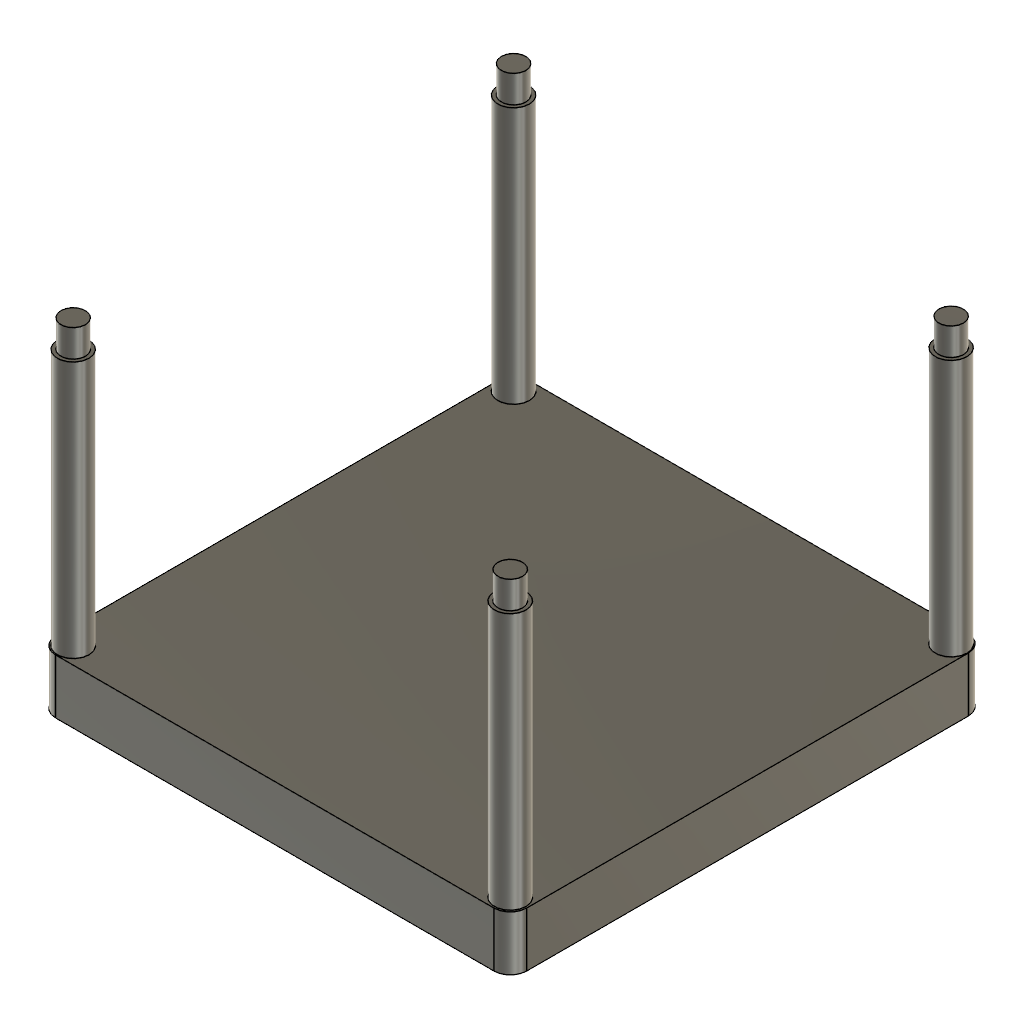
holder (Autodesk Fusion 360 design; units mm, degrees)
description: Designed by EasyEDA Pro
part number: EasyEDA PCB Model~CSds
Autodesk Fusion 360 part; units mm, degrees
sketch "Sketch1" plane through (0, 0, 34.9991) normal (0, 0, -1) x (1, 0, 0)
  line L0 (-39.1583, -39.4844) -> (41.1119, -39.4844)
  arc A0 (41.1119, -39.4844) -> (44.0992, -36.4971) centre (41.1119, -36.4971) ccw
  line L1 (44.0992, -36.4971) -> (44.0992, 44.3956)
  arc A1 (44.0992, 44.3956) -> (41.1119, 47.3829) centre (41.1119, 44.3956) ccw
  line L2 (41.1119, 47.3829) -> (-39.1583, 47.3829)
  arc A2 (-39.1583, 47.3829) -> (-42.1456, 44.3956) centre (-39.1583, 44.3956) ccw
  line L3 (-42.1456, 44.3956) -> (-42.1456, -36.4971)
  arc A3 (-42.1456, -36.4971) -> (-39.1583, -39.4844) centre (-39.1583, -36.4971) ccw
  circle A4 centre (-38.9833, 44.3231) radius 2.4
  circle A5 centre (-38.9833, -36.3221) radius 2.4
  arc A6 (-39.6818, -20.32) -> (-39.6818, -23.241) centre (-39.6818, -21.7805) ccw
  line L4 (-39.6818, -20.32) -> (-21.2668, -20.32)
  arc A7 (-21.2668, -23.241) -> (-21.2668, -20.32) centre (-21.2668, -21.7805) ccw
  line L5 (-21.2668, -23.241) -> (-39.6818, -23.241)
  line L6 (-28.7699, -27.2983) -> (-28.7699, -29.5983)
  arc A8 (-29.7699, -29.5983) -> (-28.7699, -29.5983) centre (-29.2699, -29.5983) ccw
  line L7 (-29.7699, -29.5983) -> (-29.7699, -27.2983)
  arc A9 (-28.7699, -27.2983) -> (-29.7699, -27.2983) centre (-29.2699, -27.2983) ccw
  line L8 (-23.3166, -25.9481) -> (-25.8166, -25.9481)
  arc A10 (-25.8166, -24.9481) -> (-25.8166, -25.9481) centre (-25.8166, -25.4481) ccw
  line L9 (-25.8166, -24.9481) -> (-23.3166, -24.9481)
  arc A11 (-23.3166, -25.9481) -> (-23.3166, -24.9481) centre (-23.3166, -25.4481) ccw
  line L10 (-23.4166, -31.9481) -> (-25.7166, -31.9481)
  arc A12 (-25.7166, -30.9481) -> (-25.7166, -31.9481) centre (-25.7166, -31.4481) ccw
  line L11 (-25.7166, -30.9481) -> (-23.4166, -30.9481)
  arc A13 (-23.4166, -31.9481) -> (-23.4166, -30.9481) centre (-23.4166, -31.4481) ccw
  arc A14 (-6.2927, -20.32) -> (-6.2927, -23.241) centre (-6.2927, -21.7805) ccw
  line L12 (-6.2927, -20.32) -> (37.3954, -20.32)
  arc A15 (37.3954, -23.241) -> (37.3954, -20.32) centre (37.3954, -21.7805) ccw
  line L13 (37.3954, -23.241) -> (-6.2927, -23.241)
  circle A16 centre (-5.3282, -33.9091) radius 0.51
  circle A17 centre (-5.3282, -31.3691) radius 0.51
  circle A18 centre (-5.3282, -28.8291) radius 0.51
  circle A19 centre (-5.3282, -36.4491) radius 0.51
  circle A20 centre (31.7878, -25.5631) radius 0.45
  circle A21 centre (31.7878, -30.063) radius 0.45
  circle A22 centre (31.7878, -32.2941) radius 0.45
  circle A23 centre (31.7878, -36.794) radius 0.45
  circle A24 centre (33.7878, -36.794) radius 0.45
  circle A25 centre (33.7878, -25.5631) radius 0.45
  circle A26 centre (33.7878, -30.063) radius 0.45
  circle A27 centre (33.7878, -32.2941) radius 0.45
  circle A28 centre (35.7878, -36.794) radius 0.45
  circle A29 centre (35.7878, -25.5631) radius 0.45
  circle A30 centre (35.7878, -30.063) radius 0.45
  circle A31 centre (35.7878, -32.2941) radius 0.45
  circle A32 centre (40.8999, 44.1961) radius 2.4
  circle A33 centre (41.0269, -36.3221) radius 2.4
  circle A34 centre (39.3759, -16.256) radius 0.35
  circle A35 centre (40.6459, -16.256) radius 0.35
  circle A36 centre (41.6619, -27.3051) radius 0.55
  circle A37 centre (41.6619, -32.3851) radius 0.55
  circle A38 centre (41.6619, -29.8451) radius 0.55
  circle A39 centre (41.9159, -16.256) radius 0.35
  line L14 (41.0992, -39.4875, 50) -> (-39.1527, -39.4875, 50)
  line L15 (-42.1527, -36.4875, 50) -> (-42.1527, 44.3829, 50)
  line L16 (-39.1527, 47.3829, 50) -> (41.0992, 47.3829, 50)
  line L17 (44.0992, 44.3829, 50) -> (44.0992, -36.4875, 50)
  arc A40 through (44.0992, 44.3829, 50) (43.2205, 46.5042, 50) (41.0992, 47.3829, 50)
  arc A41 through (-39.1527, 47.3829, 50) (-41.274, 46.5042, 50) (-42.1527, 44.3829, 50)
  arc A42 through (-42.1527, -36.4875, 50) (-41.274, -38.6088, 50) (-39.1527, -39.4875, 50)
  arc A43 through (41.0992, -39.4875, 50) (43.2205, -38.6088, 50) (44.0992, -36.4875, 50)
  circle A44 centre (-38.9833, -36.3221) radius 2.4
  dimension "d1" = 3
  dimension "d2" = 3
  dimension "d3" = 3
  dimension "d4" = 3
  constraint concentric A5 A44
sketch "Sketch2" plane through (0, 0, -15.0009) normal (0, 0, -1) x (1, 0, 0)
sketch "Sketch3" plane through (0, 0, -15.0009) normal (0, 0, -1) x (1, 0, 0)
extrude "Extrude1" add sketch "Sketch1" along normal blind 10 contours L14 L15 L16 L17 A40 A41 A42 A43 in plane through (0, 0, -15.0009) normal (0, 0, -1)
sketch "Sketch4" plane through (0, 0, -15.0009) normal (0, 0, 1) x (-1, 0, 0)
  arc A0 (39.1527, -39.4875) -> (42.1527, -36.4875) centre (39.1527, -36.4875) ccw
  line L0 (42.1527, -36.4875) -> (42.1527, 44.3829)
  arc A1 (42.1527, 44.3829) -> (39.1527, 47.3829) centre (39.1527, 44.3829) ccw
  line L1 (39.1527, 47.3829) -> (-41.0992, 47.3829)
  arc A2 (-41.0992, 47.3829) -> (-44.0992, 44.3829) centre (-41.0992, 44.3829) ccw
  line L2 (-44.0992, 44.3829) -> (-44.0992, -36.4875)
  arc A3 (-44.0992, -36.4875) -> (-41.0992, -39.4875) centre (-41.0992, -36.4875) ccw
  line L3 (-41.0992, -39.4875) -> (39.1527, -39.4875)
  circle A4 centre (-40.9, 44.2) radius 2.9
  circle A5 centre (39, 44.3) radius 2.9
  circle A6 centre (38.9932, -36.3084) radius 2.9
  circle A7 centre (-41.0992, -36.3084) radius 2.9
  dimension "d11" = 5.8
  dimension "d12" = 5.8
  measures "d11" diameter of A6
  measures "d12" diameter of A7
extrude "Extrude2" add sketch "Sketch4" along normal blind 47 contours A4 | A5 | A6 | A7
sketch "Sketch5" plane through (0, 0, 31.9991) normal (0, 0, 1) x (-1, 0, 0)
  circle A0 centre (-40.9, 44.2) radius 2.9
  circle A1 centre (38.9932, -36.3084) radius 2.25
  circle A2 centre (38.9932, -36.3084) radius 2.9
  circle A3 centre (39, 44.3) radius 2.25
  circle A4 centre (39, 44.3) radius 2.9
  circle A5 centre (-40.9, 44.2) radius 2.25
  circle A6 centre (-41.0992, -36.3084) radius 2.25
  circle A7 centre (-41.0992, -36.3084) radius 2.9
  dimension "d15" = 4.5
  dimension "d16" = 4.5
  dimension "d17" = 4.5
  dimension "d18" = 4.5
  constraint concentric A1 A2
  constraint concentric A3 A4
  constraint concentric A0 A5
  constraint concentric A6 A7
  measures "d15" diameter of A1
  measures "d16" diameter of A3
  measures "d17" diameter of A5
  measures "d18" diameter of A6
extrude "Extrude3" add sketch "Sketch5" along normal blind 5 contours A1 | A3 | A5 | A6
